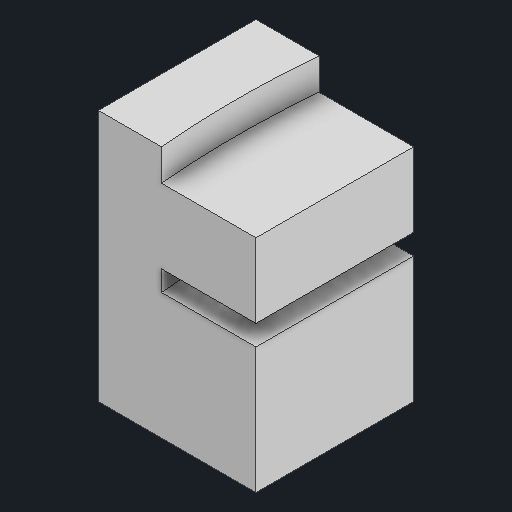
# Autodesk Inventor part: Bloco de nivelamento de MDF
Saved by Autodesk Inventor 2026.1 (Build 301233000, 233)
## iProperties
Created: 2025-10-12
Part Number: Bloco de nivelamento de MDF
Material: Genérico
Document SubType Name: Modeling
Designer: Cliente
Mass: 174.623 g
Surface Area: 230.871 cm^2
Volume: 174.623 cm^3
Density: 1 g/cm^3
Appearance: Padrão
Author: Cliente
Autodesk Inventor part; units mm, degrees
ref_plane "YZ Plane" through (0, 0, 0) normal (1, 0, 0) x (0, 1, 0)
ref_plane "XZ Plane" through (0, 0, 0) normal (0, 1, 0) x (-1, 0, 0)
sketch "Esboço1" plane through (0, 0, 0) normal (0, 1, 0) x (-1, 0, 0)
  line L0 (-25, 25) -> (25, 25)
  line L1 (25, 25) -> (25, -25)
  line L2 (25, -25) -> (-25, -25)
  line L3 (-25, -25) -> (-25, 25)
  line L4 (-25, 25) -> (25, -25) construction
  line L5 (25, 25) -> (-25, -25) construction
  point P0 (0, 0)
  dimension "d0" = 50
  dimension "d1" = 50
  constraints: 12 end point, 2 midpoint, 2 parallel, 1 horizontal, 1 perpendicular
  measures "d0" distance of L1.end L2.end
  measures "d1" distance of L0.end L1.end
extrude "Extrusão1" add sketch "Esboço1" along normal blind 80
sketch "Esboço2" plane through (0, 80, 0) normal (0, 1, 0) x (1, 0, 0)
  line L0 (25, 25) -> (-25, 25) projected
  line L1 (-25, 25) -> (-25, -25) projected
  line L2 (-25, -25) -> (25, -25) projected
  line L3 (25, -25) -> (25, 25) projected
  arc A0 (-5, 25) -> (-5, -25) centre (268.8613, 0) ccw
  point P0 (0, 0)
  dimension "d5" = 275
  dimension "d6" = 20
  constraints: 2 point on circle, 2 point on line, 1 centre point, 1 vertical alignment
  measures "d5" radius of A0
  measures "d6" distance from line of L1 A0.end
extrude "Extrusão2" cut sketch "Esboço2" against normal blind 10 contours L3 L2 A0 L0
ref_plane "Plano de trabalho1" through (0, 40, 0) normal (0, 1, 0) x (1, 0, 0)
sketch "Esboço3" plane through (0, 40, 0) normal (0, 1, 0) x (1, 0, 0)
  line L0 (-5, 25) -> (25, 25) projected
  arc A0 (-5, 25) -> (-5, -25) centre (268.8613, 0) ccw projected
  line L1 (25, -25) -> (-5, -25) projected
  line L2 (25, 25) -> (25, -25) projected
  point P0 (0, 0)
extrude "Extrusão3" cut sketch "Esboço3" along normal blind 6.5
